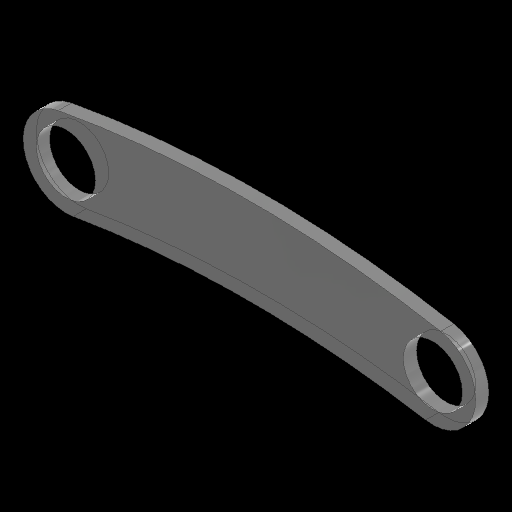
# Autodesk Inventor part: INTK_004_top bar
Saved by Autodesk Inventor 2027.1 (Build 311270010, 270A)
## iProperties
Created: 2026-11-21
Part Number: INTK_004_top bar
Material: Polycarbonate, Clear
Document SubType Name: Modeling
Designer: Stanley Ruangsuwan
Density: 1.2 g/cm^3
Appearance: Polycarbonate - Clear
Author: Stanley Ruangsuwan
Autodesk Inventor part; units mm, degrees
ref_plane "YZ Plane" through (0, 0, 0) normal (1, 0, 0) x (0, 1, 0)
ref_plane "XZ Plane" through (0, 0, 0) normal (0, 1, 0) x (-1, 0, 0)
ref_plane "XY Plane" through (0, 0, 0) normal (0, 0, 1) x (1, 0, 0)
sketch "Sketch1" plane through (0, 0, 0) normal (0, 0, 1) x (1, 0, 0)
  line L0 (0, 0) -> (177.0899, 0)
  circle A0 centre (0, 0) radius 14.2875
  circle A1 centre (177.0899, 0) radius 14.2875
  circle A2 centre (177.0899, 0) radius 20.6375
  circle A3 centre (0, 0) radius 20.6375
  arc A4 (180.8393, 20.294) -> (-3.7495, 20.294) centre (88.5449, -479.2515) ccw
  arc A5 (173.6332, -20.3459) -> (3.4567, -20.3459) centre (88.5449, -521.1693) ccw
  dimension "d1" = 28.575
  dimension "d2" = 28.575
  dimension "d7" = 6.35
  dimension "d8" = 177.0899
  dimension "d9" = 508
  constraints: 8 point on circle, 6 centre point, 3 coincident, 2 end point, 2 equal radius, 2 tangent, 1 horizontal, 1 vertical alignment
  measures "d1" diameter of A0
  measures "d2" diameter of A1
  measures "d7" radial gap between concentric circles of A1 A2
  measures "d8" distance of L0.start L0.end
  measures "d9" radius of A5
extrude "Extrusion1" add sketch "Sketch1" along normal blind 6.35
body "Solid1"
